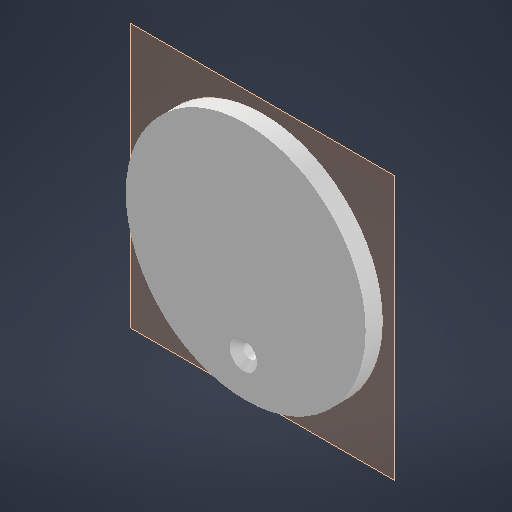
# Autodesk Inventor part: COUVERCLE2
Saved by Autodesk Inventor 2026.1 (Build 301233020, 233B)
## iProperties
Created: 2025-12-17
Part Number: COUVERCLE2
Material: Générique
Document SubType Name: Modeling
Designer: matpo
Density: 1 g/cm^3
Appearance: Par défaut
Author: matpo
Autodesk Inventor part; units mm, degrees
ref_plane "YZ Plane" through (0, 0, 0) normal (1, 0, 0) x (0, 1, 0)
ref_plane "XZ Plane" through (0, 0, 0) normal (0, 1, 0) x (-1, 0, 0)
ref_plane "XY Plane" through (0, 0, 0) normal (0, 0, 1) x (1, 0, 0)
ref_plane "Plan de construction1" through (0, 0, 0) normal (0, 0, 1) x (1, 0, 0)
sketch "Esquisse1" plane through (0, 0, 0) normal (0, 0, 1) x (1, 0, 0)
  arc A0 (19.0843, -28.0427) -> (23.293, 24.945) centre (1.6886, 0) ccw projected
  line L0 (-28.7166, -12.8267) -> (19.0843, -12.8267) projected
  arc A1 (-19.9157, 24.945) -> (-28.7166, -12.8267) centre (1.6886, 0) ccw projected
  circle A2 centre (1.6886, 0) radius 35 projected
  circle A3 centre (1.0004, -23.91) radius 2 projected
  line L1 (-1.0614, 24.945) -> (-19.9157, 24.945) projected
  line L2 (19.0843, -12.8267) -> (19.0843, -28.0427) projected
  line L3 (4.4386, 28.445) -> (4.4386, 24.945) projected
  line L4 (23.293, 24.945) -> (4.4386, 24.945) projected
  line L5 (-1.0614, 24.945) -> (-1.0614, 28.445) projected
  line L6 (-1.0614, 28.445) -> (-2.0114, 28.445) projected
  line L7 (-2.0114, 28.445) -> (-2.0114, 30.245) projected
  line L8 (-2.0114, 30.245) -> (5.3886, 30.245) projected
  line L9 (5.3886, 30.245) -> (5.3886, 28.445) projected
  line L10 (5.3886, 28.445) -> (4.4386, 28.445) projected
  point P0 (0, 0)
  point P1 (1.6886, 0)
  point P2 (1.6886, 0)
  point P3 (1.6886, 0)
extrude "Extrusion1" add sketch "Esquisse1" along normal blind 5 contours L2 L0 A1 L1 L5 L6 L7 L8 L9 L10 L3 L4 A0 | A2 | A3
sketch "Esquisse2" plane through (1.6886, 0, 0) normal (0, 0, -1) x (-1, 0, 0)
  arc A0 (-21.6043, 24.945) -> (-17.3956, -28.0427) centre (0, 0) ccw projected
  line L0 (30.4052, -12.8267) -> (-17.3956, -12.8267) projected
  arc A1 (30.4052, -12.8267) -> (21.6043, 24.945) centre (0, 0) ccw projected
  circle A2 centre (0, 0) radius 35 projected
  circle A3 centre (0.6882, -23.91) radius 2 projected
  line L1 (2.75, 24.945) -> (21.6043, 24.945) projected
  line L2 (-17.3956, -12.8267) -> (-17.3956, -28.0427) projected
  line L3 (-2.75, 28.445) -> (-2.75, 24.945) projected
  line L4 (-21.6043, 24.945) -> (-2.75, 24.945) projected
  line L5 (2.75, 24.945) -> (2.75, 28.445) projected
  line L6 (2.75, 28.445) -> (3.7, 28.445) projected
  line L7 (3.7, 28.445) -> (3.7, 30.245) projected
  line L8 (3.7, 30.245) -> (-3.7, 30.245) projected
  line L9 (-3.7, 30.245) -> (-3.7, 28.445) projected
  line L10 (-3.7, 28.445) -> (-2.75, 28.445) projected
  arc A4 (-21.3795, 24.345) -> (-17.9956, -26.9428) centre (0, 0) ccw
  line L11 (-21.3795, 24.345) -> (-2.15, 24.345)
  line L12 (-2.15, 24.345) -> (-2.15, 29.045)
  line L13 (-2.15, 29.045) -> (-3.1, 29.045)
  line L14 (-3.1, 29.045) -> (-3.1, 29.645)
  line L15 (-3.1, 29.645) -> (3.1, 29.645)
  line L16 (3.1, 29.645) -> (3.1, 29.045)
  line L17 (3.1, 29.045) -> (2.15, 29.045)
  line L18 (2.15, 29.045) -> (2.15, 24.345)
  line L19 (2.15, 24.345) -> (21.3795, 24.345)
  arc A5 (30.0045, -12.2267) -> (21.3795, 24.345) centre (0, 0) ccw
  line L20 (30.0045, -12.2267) -> (-17.9956, -12.2267)
  line L21 (-17.9956, -12.2267) -> (-17.9956, -26.9428)
  dimension "d11" = 0.6
  constraints: 22 end point, 4 point on circle, 2 centre point, 12 other
  measures "d11" distance between parallel lines of L2 L21
extrude "Extrusion2" add sketch "Esquisse2" along normal blind 1 contours L11 L12 L13 L14 L15 L16 L17 L18 L19 A5 L20 L21 A4
sketch "Esquisse3" plane through (1.6886, 0, 5) normal (0, 0, 1) x (1, 0, 0)
  circle A0 centre (-0.6882, -23.91) radius 2 projected
  point P0 (-1.6886, 0)
extrude "Extrusion3" cut sketch "Esquisse3" against normal through all
chamfer "Chanfrein1" distance 2 angle 45 1 edges at (-0.9996, -23.91, 5)
